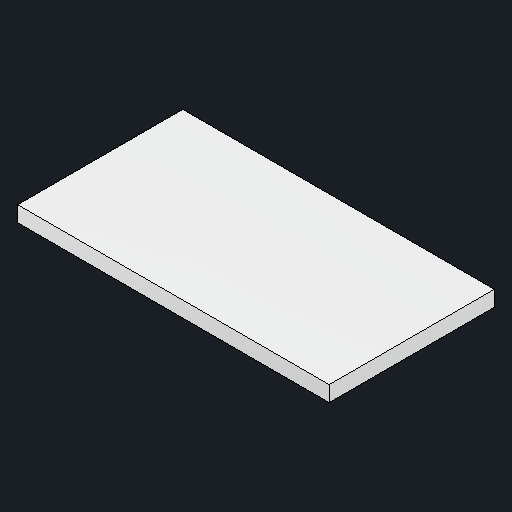
# Autodesk Inventor part: Echelle support bottom plate
Saved by Autodesk Inventor 2027.1 (Build 311270010, 270A)
## iProperties
Created: 2026-11-21
Part Number: Echelle support bottom plate
Material: Aluminum 6061
Description: Echelle support upright front bottom plate; photo-sized mockup
Document SubType Name: Modeling
Designer: queezz
Density: 2.7 g/cm^3
Appearance: Aluminum - Flat
Mass: 572.4 g
Surface Area: 485.2 cm^2
Volume: 212 cm^3
SupportWidth: 200,000 mm
StockThickness: 10,000 mm
SupportHeight: 140,000 mm
RoofAngle: 26,50 deg
RoofFoot: 38,360 mm
ArmHeight: 106,000 mm
ArmRoot: 70,000 mm
ArmTip: 87,000 mm
WindowWidth: 50,000 mm
WindowLength: 100,000 mm
WindowCentreHeight: 75,000 mm
BaseDepth: 10,000 mm
RoofEndHeight: 131,550 mm
RoofEndDepth: 103,948 mm
Author: queezz
Autodesk Inventor part; units mm, degrees
ref_plane "YZ Plane" through (0, 0, 0) normal (1, 0, 0) x (0, 1, 0)
ref_plane "XZ Plane" through (0, 0, 0) normal (0, 1, 0) x (-1, 0, 0)
ref_plane "XY Plane" through (0, 0, 0) normal (0, 0, 1) x (1, 0, 0)
sketch "Upright front bottom plate - common dimensions" plane through (0, 0, 0) normal (1, 0, 0) x (0, 1, 0)
  line L0 (0, 0) -> (10, 0)
  line L1 (10, 0) -> (10, 106)
  line L2 (10, 106) -> (0, 106)
  line L3 (0, 106) -> (0, 0)
  dimension "d6" = 10
  dimension "d7" = 10
  dimension "d8" = 106
  dimension "d9" = 106
  constraints: 8 end point, 1 horizontal alignment, 1 vertical alignment, 1 other
  measures "d6" distance of L0.start L0.end
  measures "d7" horizontal distance of L0.start L1.end
  measures "d8" vertical distance of L0.start L1.end
  measures "d9" distance of L0.start L2.end
extrude "Upright rectangular plate" add sketch "Upright front bottom plate - common dimensions" along normal blind 200
equation "\"d6\" = StockThickness"
equation "\"d7\" = StockThickness"
equation "\"d8\" = ArmHeight"
equation "\"d9\" = ArmHeight"
equation "\"d10\" = SupportWidth"
equation "\"SupportWidth\" = 200"
equation "\"StockThickness\" = 10"
equation "\"SupportHeight\" = 140"
equation "\"RoofAngle\" = 26.5deg"
equation "\"RoofFoot\" = 38.36"
equation "\"ArmHeight\" = 106"
equation "\"ArmRoot\" = 70"
equation "\"ArmTip\" = 87"
equation "\"WindowWidth\" = 50"
equation "\"WindowLength\" = 100"
equation "\"WindowCentreHeight\" = 75"
equation "\"BaseDepth\" = StockThickness"
body "Solid2"
